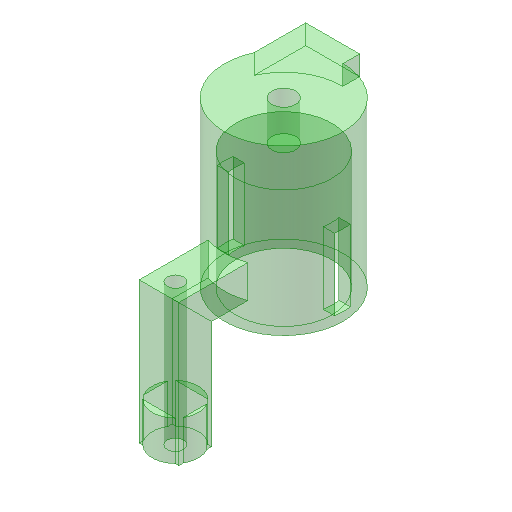
# Autodesk Inventor part: OT2-Pipette V0.5 - yoke eject variant
Saved by Autodesk Inventor 2025.5 (Build 295498000, 498)
## iProperties
Created: 2026-11-20
Part Number: OT2-Pipette V0.5 - yoke eject variant
Material: Generisch
Description: printed yoke, eject variant: skirt for the spring pad, arm with M3 adjust screw over the ejector
Document SubType Name: Modeling
Designer: benir
Density: 1 g/cm^3
Appearance: Green
Author: benir
Autodesk Inventor part; units mm, degrees
ref_plane "y=top_y - disc_h" through (0, 95, 0) normal (0, 1, 0) x (-1, 0, 0)
sketch "disc" plane through (0, 95, 0) normal (0, 1, 0) x (-1, 0, 0)
  circle A0 centre (-8.2, -3.46) radius 9
  point P0 (0, 0)
  dimension "d3" = 3.46
  dimension "d4" = 8.2
  dimension "d5" = 18
  constraints: 1 centre point
  measures "d3" vertical distance of point (0, 0) A0.centre
  measures "d4" horizontal distance of point (0, 0) A0.centre
  measures "d5" diameter of A0
extrude "Extrusion2" add sketch "disc" along normal blind 7
ref_plane "y=skirt_y0" through (0, 77, 0) normal (0, 1, 0) x (-1, 0, 0)
sketch "skirt" plane through (0, 77, 0) normal (0, 1, 0) x (-1, 0, 0)
  circle A0 centre (-8.2, -3.46) radius 9
  point P0 (0, 0)
  dimension "d9" = 3.46
  dimension "d10" = 8.2
  dimension "d11" = 18
  constraints: 1 centre point
  measures "d9" vertical distance of point (0, 0) A0.centre
  measures "d10" horizontal distance of point (0, 0) A0.centre
  measures "d11" diameter of A0
extrude "Extrusion3" add sketch "skirt" along normal blind 18
ref_plane "y=skirt_y0 - cut_over" through (0, 76, 0) normal (0, 1, 0) x (-1, 0, 0)
sketch "skirt bore" plane through (0, 76, 0) normal (0, 1, 0) x (-1, 0, 0)
  circle A0 centre (-8.2, -3.46) radius 7.3
  point P0 (0, 0)
  dimension "d15" = 3.46
  dimension "d16" = 8.2
  dimension "d17" = 14.6
  constraints: 1 centre point
  measures "d15" vertical distance of point (0, 0) A0.centre
  measures "d16" horizontal distance of point (0, 0) A0.centre
  measures "d17" diameter of A0
extrude "Extrusion4" cut sketch "skirt bore" along normal blind 19
ref_plane "y=skirt_y0 + slot_y0" through (0, 78.3, 0) normal (0, 1, 0) x (-1, 0, 0)
sketch "pin slots" plane through (0, 78.3, 0) normal (0, 1, 0) x (-1, 0, 0)
  line L0 (1.8, -4.66) -> (-18.2, -4.66)
  line L1 (-18.2, -4.66) -> (-18.2, -2.26)
  line L2 (-18.2, -2.26) -> (1.8, -2.26)
  line L3 (1.8, -2.26) -> (1.8, -4.66)
  line L4 (0, -16.06) -> (0, 9.14) projected
  line L5 (5.8, 0) -> (-22.2, 0) projected
  point P0 (0, 0)
  dimension "d21" = 20
  dimension "d22" = 2.4
  dimension "d23" = 1.8
  dimension "d24" = 4.66
  constraints: 8 end point, 2 parallel, 1 horizontal, 1 perpendicular
  measures "d21" distance of L0.start L0.end
  measures "d22" distance of L2.end L0.start
  measures "d23" horizontal distance of point (0, 0) L2.end
  measures "d24" vertical distance of point (0, 0) L0.start
extrude "Extrusion5" cut sketch "pin slots" along normal blind 10.9
ref_plane "y=arm_y0" through (0, 81, 0) normal (0, 1, 0) x (-1, 0, 0)
sketch "arm" plane through (0, 81, 0) normal (0, 1, 0) x (-1, 0, 0)
  line L0 (-5.2, 3.84) -> (-11.2, 3.84)
  line L1 (-11.2, 3.84) -> (-11.2, 15.54)
  line L2 (-11.2, 15.54) -> (-5.2, 15.54)
  line L3 (-5.2, 15.54) -> (-5.2, 3.84)
  line L4 (0, -18.06) -> (0, 21.14) projected
  line L5 (4.4, 0) -> (-20.8, 0) projected
  point P0 (0, 0)
  dimension "d28" = 6
  dimension "d29" = 11.7
  dimension "d30" = 5.2
  dimension "d31" = 3.84
  constraints: 8 end point, 2 parallel, 1 horizontal, 1 perpendicular
  measures "d28" distance of L0.start L0.end
  measures "d29" distance of L2.end L0.start
  measures "d30" horizontal distance of point (0, 0) L2.end
  measures "d31" vertical distance of point (0, 0) L0.start
extrude "Extrusion6" add sketch "arm" along normal blind 5
ref_plane "y=arm_boss_y" through (0, 64.5, 0) normal (0, 1, 0) x (-1, 0, 0)
sketch "arm drop" plane through (0, 64.5, 0) normal (0, 1, 0) x (-1, 0, 0)
  line L0 (-5.2, 10.54) -> (-11.2, 10.54)
  line L1 (-11.2, 10.54) -> (-11.2, 15.54)
  line L2 (-11.2, 15.54) -> (-5.2, 15.54)
  line L3 (-5.2, 15.54) -> (-5.2, 10.54)
  line L4 (0, -18.06) -> (0, 21.14) projected
  line L5 (4.4, 0) -> (-20.8, 0) projected
  point P0 (0, 0)
  dimension "d35" = 6
  dimension "d36" = 5
  dimension "d37" = 5.2
  dimension "d38" = 10.54
  constraints: 8 end point, 2 parallel, 1 horizontal, 1 perpendicular
  measures "d35" distance of L0.start L0.end
  measures "d36" distance of L2.end L0.start
  measures "d37" horizontal distance of point (0, 0) L2.end
  measures "d38" vertical distance of point (0, 0) L0.start
extrude "Extrusion7" add sketch "arm drop" along normal blind 21.5
sketch "screw boss" plane through (0, 64.5, 0) normal (0, 1, 0) x (-1, 0, 0)
  circle A0 centre (-8.2, 13.04) radius 3.5
  point P0 (0, 0)
  dimension "d41" = 13.04
  dimension "d42" = 8.2
  dimension "d43" = 7
  constraints: 1 centre point
  measures "d41" vertical distance of point (0, 0) A0.centre
  measures "d42" horizontal distance of point (0, 0) A0.centre
  measures "d43" diameter of A0
extrude "adjust screw boss" add sketch "screw boss" along normal blind 6
ref_plane "y=arm_boss_y - cut_over" through (0, 63.5, 0) normal (0, 1, 0) x (-1, 0, 0)
sketch "adjust screw hole" plane through (0, 63.5, 0) normal (0, 1, 0) x (-1, 0, 0)
  circle A0 centre (-8.2, 13.04) radius 1.25
  point P0 (0, 0)
  dimension "d47" = 13.04
  dimension "d48" = 8.2
  dimension "d49" = 2.5
  constraints: 1 centre point
  measures "d47" vertical distance of point (0, 0) A0.centre
  measures "d48" horizontal distance of point (0, 0) A0.centre
  measures "d49" diameter of A0
extrude "M3 adjust screw hole" cut sketch "adjust screw hole" along normal blind 23.5
ref_plane "y=top_y - tab_h" through (0, 99, 0) normal (0, 1, 0) x (-1, 0, 0)
sketch "switch tab" plane through (0, 99, 0) normal (0, 1, 0) x (-1, 0, 0)
  line L0 (0, -15) -> (-8.2, -15)
  line L1 (-8.2, -15) -> (-8.2, -3.46)
  line L2 (-8.2, -3.46) -> (0, -3.46)
  line L3 (0, -3.46) -> (0, -15)
  line L4 (0, -21.308) -> (0, 22.848) projected
  line L5 (4.4, 0) -> (-20.8, 0) projected
  point P0 (0, 0)
  dimension "d53" = 8.2
  dimension "d54" = 11.54
  dimension "d55" = 15
  constraints: 8 end point, 2 parallel, 1 collinear, 1 horizontal, 1 perpendicular
  measures "d53" distance of L0.start L0.end
  measures "d54" distance of L2.end L0.start
  measures "d55" distance of point (0, 0) L0.start
extrude "Extrusion10" add sketch "switch tab" along normal blind 3
ref_plane "y=top_y - insert_m25_depth" through (0, 96, 0) normal (0, 1, 0) x (-1, 0, 0)
sketch "M2.5 insert hole" plane through (0, 96, 0) normal (0, 1, 0) x (-1, 0, 0)
  circle A0 centre (-8.2, -3.46) radius 1.8
  point P0 (0, 0)
  dimension "d59" = 3.46
  dimension "d60" = 8.2
  dimension "d61" = 3.6
  constraints: 1 centre point
  measures "d59" vertical distance of point (0, 0) A0.centre
  measures "d60" horizontal distance of point (0, 0) A0.centre
  measures "d61" diameter of A0
extrude "Extrusion11" cut sketch "M2.5 insert hole" along normal blind 7
equation "\"d3\" = -pip_z"
equation "\"d4\" = pip_x"
equation "\"d5\" = yoke_d"
equation "\"d6\" = disc_h"
equation "\"d9\" = -pip_z"
equation "\"d10\" = pip_x"
equation "\"d11\" = yoke_d"
equation "\"d12\" = -disc_h + top_y - skirt_y0"
equation "\"d15\" = -pip_z"
equation "\"d16\" = pip_x"
equation "\"d17\" = skirt_id"
equation "\"d18\" = -skirt_y0 + top_y - disc_h + cut_over"
equation "\"d21\" = 2 * slot_half_len + 0 * pip_x"
equation "\"d22\" = 2 * slot_hw + 0 * pip_z"
equation "\"d23\" = slot_half_len - pip_x"
equation "\"d24\" = slot_hw - pip_z"
equation "\"d25\" = -skirt_y0 + slot_y1 - slot_y0"
equation "\"d28\" = arm_w + 0 * pip_x"
equation "\"d29\" = 0.5 * arm_t + 0 * pip_z + arm_r - 0.5 * skirt_id"
equation "\"d30\" = pip_x - 0.5 * arm_w"
equation "\"d31\" = pip_z + 0.5 * skirt_id"
equation "\"d32\" = arm_t"
equation "\"d35\" = arm_w + 0 * pip_x"
equation "\"d36\" = arm_t + 0 * pip_z + 0 * arm_r"
equation "\"d37\" = pip_x - 0.5 * arm_w"
equation "\"d38\" = arm_r + pip_z - 0.5 * arm_t"
equation "\"d39\" = arm_t + arm_y0 - arm_boss_y"
equation "\"d41\" = pip_z + arm_r"
equation "\"d42\" = pip_x"
equation "\"d43\" = boss_d"
equation "\"d44\" = boss_h"
equation "\"d47\" = pip_z + arm_r"
equation "\"d48\" = pip_x"
equation "\"d49\" = m3_tap_d"
equation "\"d50\" = -arm_boss_y + arm_y0 + arm_t + 2 * cut_over"
equation "\"d53\" = pip_x - tab_x0"
equation "\"d54\" = pip_z - tab_z_in - sw_z0"
equation "\"d55\" = -tab_z_in - sw_z0"
equation "\"d56\" = tab_h"
equation "\"d59\" = -pip_z"
equation "\"d60\" = pip_x"
equation "\"d61\" = insert_m25"
equation "\"d62\" = insert_m25_depth + cut_over"
equation "\"yoke_d\" = 18"
equation "\"disc_h\" = 7"
equation "\"top_y\" = 102"
equation "\"skirt_y0\" = 77"
equation "\"skirt_id\" = 14.6"
equation "\"cut_over\" = 1"
equation "\"slot_half_len\" = 10"
equation "\"pip_x\" = 8.2"
equation "\"slot_hw\" = 1.2"
equation "\"pip_z\" = -3.46"
equation "\"slot_y1\" = 89.2"
equation "\"slot_y0\" = 1.3"
equation "\"arm_w\" = 6"
equation "\"arm_t\" = 5"
equation "\"arm_r\" = 16.5"
equation "\"arm_y0\" = 81"
equation "\"arm_boss_y\" = 64.5"
equation "\"boss_d\" = 7"
equation "\"boss_h\" = 6"
equation "\"m3_tap_d\" = 2.5"
equation "\"tab_x0\" = 0"
equation "\"tab_z_in\" = 1"
equation "\"sw_z0\" = -16"
equation "\"tab_h\" = 3"
equation "\"insert_m25\" = 3.6"
equation "\"insert_m25_depth\" = 6"
body "Solid2"
